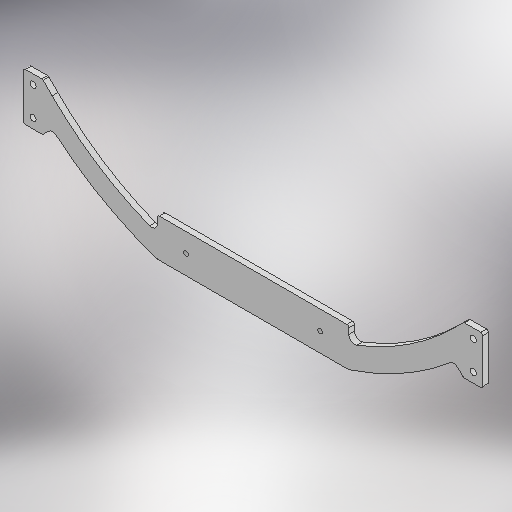
# Autodesk Inventor part: AP3.0_E-STOP-camera
Saved by Autodesk Inventor 2025.3 (Build 293356030, 356C)
## iProperties
Created: 2026-09-02
Part Number: AP3.0_E-STOP-camera
Material: 一般
Document SubType Name: Sheet Metal
Designer: ibuki_ono
Density: 1 g/cm^3
Sheet Metal Rule: Default_mm
Appearance: 既定
Author: ibuki_ono
Autodesk Inventor part; units mm, degrees
ref_plane "YZ Plane" through (0, 0, 0) normal (1, 0, 0) x (0, 1, 0)
ref_plane "XZ Plane" through (0, 0, 0) normal (0, 1, 0) x (-1, 0, 0)
ref_plane "XY Plane" through (0, 0, 0) normal (0, 0, 1) x (1, 0, 0)
sketch "スケッチ1" plane through (0, 0, 0) normal (0, 0, 1) x (1, 0, 0)
  line L0 (120, -12.5) -> (-120, -12.5)
  line L1 (-120, -12.5) -> (-120, 12.5)
  line L2 (-120, 12.5) -> (120, 12.5)
  line L3 (120, 12.5) -> (120, -12.5)
  line L4 (120, -12.5) -> (-120, 12.5) construction
  line L5 (-120, -12.5) -> (120, 12.5) construction
  line L6 (105, -7.5) -> (-105, -7.5)
  line L7 (-105, -7.5) -> (-105, 7.5)
  line L8 (-105, 7.5) -> (105, 7.5)
  line L9 (105, 7.5) -> (105, -7.5)
  line L10 (105, -7.5) -> (-105, 7.5) construction
  line L11 (-105, -7.5) -> (105, 7.5) construction
  line L12 (-120, -12.5) -> (-110, -12.5)
  line L13 (-110, -12.5) -> (-110, 12.5)
  line L14 (-110, 12.5) -> (-120, 12.5)
  line L15 (-120, 12.5) -> (-120, -12.5)
  line L16 (120, -12.5) -> (110, -12.5)
  line L17 (110, -12.5) -> (110, 12.5)
  line L18 (110, 12.5) -> (120, 12.5)
  line L19 (120, 12.5) -> (120, -12.5)
  line L20 (-105, -7.5) -> (-110, -12.5)
  line L21 (-105, 7.5) -> (-110, 12.5)
  line L22 (105, 7.5) -> (110, 12.5)
  line L23 (105, -7.5) -> (110, -12.5)
  arc A0 (-105, 7.5) -> (105, 7.5) centre (0, 112.5) ccw
  line L24 (-50, -38.91) -> (50, -38.91)
  line L25 (50, -38.91) -> (50, -18.91)
  line L26 (50, -18.91) -> (-50, -18.91)
  line L27 (-50, -18.91) -> (-50, -38.91)
  arc A1 (-105, -7.5) -> (105, -7.5) centre (0, 112.5) ccw
  line L28 (-50, -38.91) -> (-50, -38.91)
  point P0 (0, 0)
  point P1 (0, 7.5)
  point P2 (50, -27.3213)
  point P3 (-50, -27.3213)
  point P4 (0, -46.9522)
  point P5 (63.0286, -21.9522)
  point P6 (80.1561, -12.5)
  point P7 (-80.1561, -12.5)
  point P8 (-98.9949, -12.5)
  point P9 (0, -18.91)
  point P10 (-87.4643, -7.5)
  point P11 (87.4643, -7.5)
  point P12 (98.9949, -12.5)
  point P13 (50, -38.91)
  point P14 (-50, -38.91)
  point P15 (39.6172, -41.9522)
  dimension "d0" = 240
  dimension "d1" = 25
  dimension "d2" = 210
  dimension "d3" = 15
  dimension "d4" = 10
  dimension "d5" = 10
  dimension "d18" = 20
  dimension "d19" = 100
  measures "d0" distance of L1.end L2.end
  measures "d1" distance of L0.end L1.end
  measures "d2" distance of L7.end L8.end
  measures "d3" distance of L6.end L7.end
  measures "d4" distance of L14.end L13.end
  measures "d5" distance of L17.end L18.end
  measures "d18" distance of L24.end L25.end
  measures "d19" distance of L25.end L26.end
extrude "プレート1" add sketch "スケッチ1" along normal blind 3 contours L0 L17 L2 L3 | L23 L9 L22 L17 | A1 L25 A0 L0 | L0 A0 L6 A1 | L6 A0 L9 | L24 L27 A0 L25 | L13 L0 L1 L2 | L21 L7 L20 L13 | A0 L27 A1 L0 | L0 A1 L6 A0 | A0 L27 L26 L25 | A0 L6 L7
sketch "スケッチ2" plane through (0, 0, 3) normal (0, 0, 1) x (1, 0, 0)
  line L0 (-115, -12.5) -> (-115, 12.5) construction
  line L1 (-120, 12.5) -> (-110, 12.5) projected
  line L2 (-110, -12.5) -> (-120, -12.5) projected
  point P0 (0, 0)
  point P1 (-115, 7.5)
  point P2 (-115, -7.5)
  point P3 (-115, 0)
  dimension "d9" = 7.5
  dimension "d10" = 7.5
  constraints: 3 midpoint, 2 end point, 2 point on line
  measures "d9" distance of point (-115, 0) point (-115, 7.5)
  measures "d10" distance of point (-115, -7.5) point (-115, 0)
hole "穴1" at (-115, 7.5, 3) at (-115, -7.5, 3) direction (0, 0, -1) diameter 3.2 end through all
sketch "スケッチ3" plane through (0, 0, 3) normal (0, 0, 1) x (1, 0, 0)
  line L0 (-50, -27.3213) -> (-50, -18.91) projected
  line L1 (50, -18.91) -> (50, -27.3213) projected
  line L2 (-50, -18.91) -> (50, -18.91) construction
  line L3 (-50, -28.91) -> (50, -28.91) construction
  line L4 (50, -38.91) -> (-50, -38.91) construction
  point P0 (0, 0)
  point P1 (-35, -28.91)
  point P2 (35, -28.91)
  point P3 (0, -28.91)
  point P4 (-50, -41.9522)
  point P5 (63.0286, -21.9522)
  point P6 (105, -7.5)
  point P7 (-50, -38.91)
  point P8 (0, -28.91)
  point P9 (-50, -38.91)
  point P10 (-50, -38.91)
  dimension "d21" = 35
  dimension "d22" = 35
  dimension "d37" = 10
  constraints: 3 point on line, 2 end point, 1 coincident, 1 horizontal, 1 midpoint, 4 other
  measures "d21" distance of point (-35, -28.91) point (0, -28.91)
  measures "d22" distance of point (0, -28.91) point (35, -28.91)
hole "穴2" at (-35, -28.91, 3) at (35, -28.91, 3) direction (0, 0, -1) diameter 2.5 end through all
thread "ねじ1" size "M3x0.5" class "6H" standard "ISO Metric profile" full length
thread "ねじ2" size "M3x0.5" class "6H" standard "ISO Metric profile" full length
mirror "ミラー1" about plane through (0, 0, 0) normal (1, 0, 0) of "穴1"
fillet "フィレット1" radius 1 12 edges at (-120, -12.5, 1.5) (-120, 12.5, 1.5) (-110, 12.5, 1.5) (-50, -18.91, 1.5) (110, 12.5, 1.5) (120, 12.5, 1.5) (120, -12.5, 1.5) (110, -12.5, 1.5) (50, -18.91, 1.5) (-110, -12.5, 1.5) (-50, -38.91, 1.5) (50, -38.91, 1.5)
fillet "フィレット2" radius 3 4 edges at (105, -7.5, 1.5) (-50, -27.3213, 1.5) (-105, -7.5, 1.5) (50, -27.3213, 1.5)
equation "\"d10\" = d9"
equation "\"d16\" = Thickness"
equation "\"d8\" = Thickness"
equation "\"d22\" = d21"
equation "\"Thickness\" = 3"
